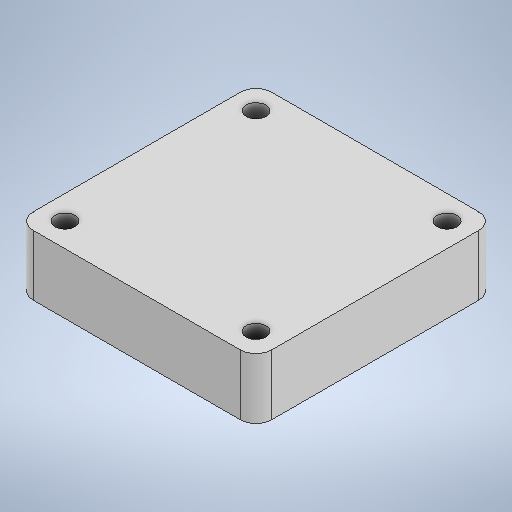
# Autodesk Inventor part: FAN
Saved by Autodesk Inventor 2025.3 (Build 293356000, 356)
## iProperties
Created: 2026-09-09
Part Number: FAN
Material: 常规
Document SubType Name: Modeling
Designer: shfzf
Density: 1 g/cm^3
Appearance: 默认
Author: shfzf
Autodesk Inventor part; units mm, degrees
ref_plane "YZ Plane" through (0, 0, 0) normal (1, 0, 0) x (0, 1, 0)
ref_plane "XZ Plane" through (0, 0, 0) normal (0, 1, 0) x (-1, 0, 0)
ref_plane "XY Plane" through (0, 0, 0) normal (0, 0, 1) x (1, 0, 0)
sketch "草图1" plane through (0, 0, 0) normal (0, 1, 0) x (-1, 0, 0)
  line L0 (15, 15) -> (-15, 15)
  line L1 (-15, 15) -> (-15, -15)
  line L2 (-15, -15) -> (15, -15)
  line L3 (15, -15) -> (15, 15)
  point P0 (0, 0)
  point P1 (15, 0)
  point P2 (0, 15)
  dimension "d0" = 30
  dimension "d1" = 30
  dimension "d2" = 30
  constraints: 8 end point, 2 midpoint, 2 parallel, 1 horizontal, 1 horizontal alignment, 1 perpendicular, 1 vertical alignment
  measures "d0" distance of L2.end L1.end
  measures "d1" distance of L0.start L0.end
  measures "d2" distance of L2.end L0.start
extrude "拉伸1" add sketch "草图1" along normal blind 7.6
sketch "草图2" plane through (0, 7.6, 0) normal (0, 1, 0) x (1, 0, 0)
  line L0 (12, 12) -> (-12, 12)
  line L1 (-12, 12) -> (-12, -12)
  line L2 (-12, -12) -> (12, -12)
  line L3 (12, -12) -> (12, 12)
  line L4 (12, 12) -> (-12, -12) construction
  line L5 (-12, 12) -> (12, -12) construction
  circle A0 centre (-12, -12) radius 1.25
  circle A1 centre (12, -12) radius 1.25
  circle A2 centre (12, 12) radius 1.25
  circle A3 centre (-12, 12) radius 1.25
  point P0 (0, 0)
  dimension "d5" = 24
  dimension "d6" = 24
  dimension "d7" = 2.5
  dimension "d10" = 360
  constraints: 12 end point, 4 centre point, 2 midpoint, 2 parallel, 1 coincident, 1 horizontal, 1 perpendicular, 9 other
  measures "d5" distance of L2.end L1.end
  measures "d6" distance of L0.end L1.end
  measures "d7" diameter of A0
extrude "拉伸2" cut sketch "草图2" against normal through all contours A3 L1 L0 | L0 L1 A3 | A2 L3 L0 | L0 L3 A2 | A0 L2 L1 | L1 L2 A0 | A1 L2 L3 | L3 L2 A1
fillet "圆角1" radius 2 4 edges at (-15, 3.8, 15) (15, 3.8, 15) (15, 3.8, -15) (-15, 3.8, -15)
